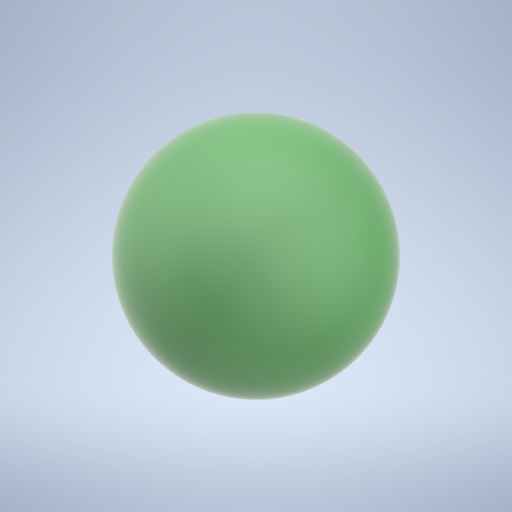
# Autodesk Inventor part: Ball
Saved by Autodesk Inventor 2023 (Build 270158000, 158)
## iProperties
Created: 2024-03-28
Part Number: Ball
Material: Polystyrene
Document SubType Name: Modeling
Designer: BenFr
Density: 1.021 g/cm^3
Appearance: Smooth - White
Mass: 146.813 g
Surface Area: 132.732 cm^2
Volume: 143.793 cm^3
Author: BenFr
Autodesk Inventor part; units mm, degrees
ref_plane "YZ Plane" through (0, 0, 0) normal (1, 0, 0) x (0, 1, 0)
ref_plane "XZ Plane" through (0, 0, 0) normal (0, 1, 0) x (-1, 0, 0)
ref_plane "XY Plane" through (0, 0, 0) normal (0, 0, 1) x (1, 0, 0)
sketch "Sketch1" plane through (0, 0, 0) normal (0, 1, 0) x (-1, 0, 0)
  circle A0 centre (0, 0) radius 32.5
  line L0 (32.5, 0) -> (-32.5, 0)
  dimension "d0" = 65
  constraints: 2 end point, 2 point on circle, 1 centre point, 1 coincident, 1 horizontal
  measures "d0" diameter of A0
revolve "Revolution1" add sketch "Sketch1" angle 360 about axis through (-32.5, 0, 0) along (1, 0, 0) picked at (9.5924, 5.0345) contours L0 A0
body "Solid1"
